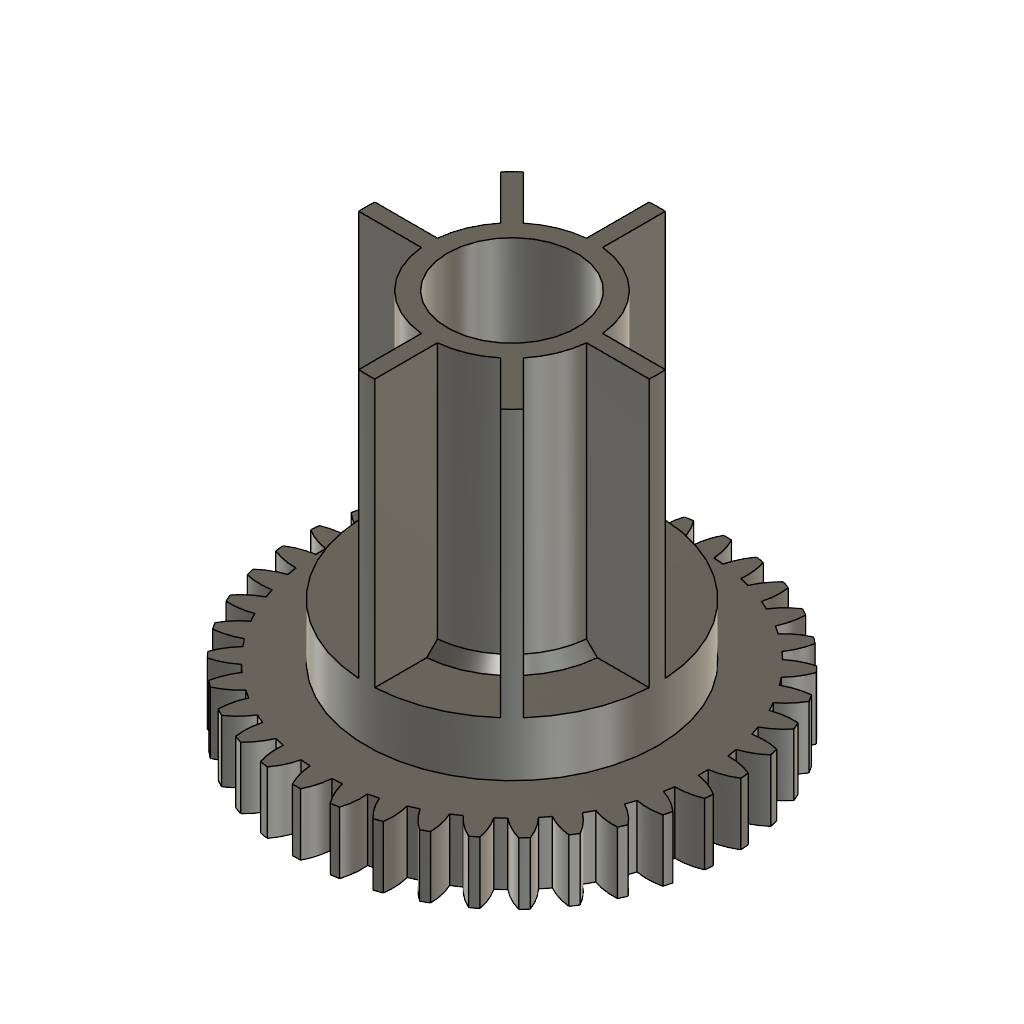
Roue_Store_D27 (Autodesk Fusion 360 design; units mm, degrees)
Autodesk Fusion 360 part; units mm, degrees
sketch "Esquisse1" plane through (0, 0, 0) normal (0, 0, 1) x (1, 0, 0)
  circle A0 centre (0, 0) radius 17.75
  dimension "d1" = 35.5
  measures "d1" diameter of A0
extrude "Extrusion1" add sketch "Esquisse1" along normal blind 5.75
sketch "Esquisse2" plane through (0, 0, 0) normal (0, 0, 1) x (1, 0, 0)
  circle A0 centre (0, 0) radius 13.5
  dimension "d4" = 27
  measures "d4" diameter of A0
extrude "Extrusion2" add sketch "Esquisse2" along normal blind 5.05 from surface at 5.75
sketch "Esquisse3" plane through (0, 0, 0) normal (0, 0, 1) x (1, 0, 0)
  circle A0 centre (0, 0) radius 7.7
  dimension "d8" = 15.4
  measures "d8" diameter of A0
extrude "Extrusion3" add sketch "Esquisse3" along normal blind 24.8 from surface at 10.8
sketch "Esquisse4" plane through (0, 0, 0) normal (0, 0, 1) x (1, 0, 0)
  circle A0 centre (0, 0) radius 11
  dimension "d12" = 22
  measures "d12" diameter of A0
extrude "Extrusion4" cut sketch "Esquisse4" along normal blind 5.5
sketch "Esquisse5" plane through (0, 0, 0) normal (0, 0, 1) x (1, 0, 0)
  circle A0 centre (0, 0) radius 3
  dimension "d15" = 6
  measures "d15" diameter of A0
extrude "Extrusion5" cut sketch "Esquisse5" along normal through all
sketch "Esquisse6" plane through (0, 0, 0) normal (0, 0, 1) x (1, 0, 0)
  circle A0 centre (0, 0) radius 6
  dimension "d17" = 12
  measures "d17" diameter of A0
extrude "Extrusion6" cut sketch "Esquisse6" against normal blind 20 from surface at 35.6
chamfer "Chanfrein1" distance 1 angle 45 1 edges at (-7.1789, 2.7844, 10.8) tangent chain off
chamfer "Chanfrein2" distance 1.4 angle 45 1 edges at (-5.594, 2.1697, 15.6) tangent chain off
sketch "Esquisse7" plane through (0, 0, 0) normal (0, 0, 1) x (1, 0, 0)
  arc A0 (0.3802, 19.9957) -> (-0.3768, 19.9957) centre (0.0017, -0.0007) ccw
  arc A1 (1.0258, 17.4199) -> (-1.0222, 17.4199) centre (0.0018, 0) ccw
  arc A2 (1.0258, 17.4199) -> (0.3802, 19.9957) centre (-4.7875, 17.3315) ccw
  arc A3 (-0.3768, 19.9957) -> (-1.0222, 17.4199) centre (4.7912, 17.3321) ccw
  dimension "d23" = 40
  dimension "d24" = 34.9
  dimension "d25" = 5.814
  dimension "d26" = 0.757
  dimension "d27" = 2.048
  constraint coincident A0.start A2.end
  constraint coincident A1.start A2.start
  constraint coincident A0.end A3.start
  constraint coincident A1.end A3.end
  constraint horizontal A0.start A0.end
  constraint horizontal A1.start A1.end
  constraint equal A2 A3
  measures "d23" diameter of A0
  measures "d24" diameter of A1
  measures "d25" radius of A2
  measures "d26" horizontal distance of A0.start A0.end
  measures "d27" horizontal distance of A1.start A1.end
extrude "Extrusion7" add sketch "Esquisse7" along normal blind 5.75
pattern_circular "Réseau C1" count 38 over 360 about axis through (0, 0, 1.75) along (0, 0, 1) of "Extrusion7"
sketch "Esquisse8" plane through (0, 0, 0) normal (0, 0, 1) x (1, 0, 0)
  arc A0 (13.4792, -0.75) -> (13.4792, 0.75) centre (0, 0) ccw
  arc A1 (6.9597, -0.75) -> (6.9597, 0.75) centre (0, 0) ccw
  line L0 (13.4792, 0.75) -> (6.9597, 0.75)
  line L1 (13.4792, -0.75) -> (6.9597, -0.75)
  dimension "d32" = 27
  dimension "d33" = 14
  dimension "d34" = 1.5
  dimension "d35" = 0.75
  constraint horizontal L0
  constraint horizontal L1
  measures "d32" diameter of A0
  measures "d33" diameter of A1
  measures "d34" vertical distance of A0.start A0.end
  measures "d35" vertical distance of A0.centre A0.end
extrude "Extrusion8" add sketch "Esquisse8" along normal blind 24.8 from surface at 10.8
pattern_circular "Réseau C2" count 4 over 360 about axis through (0, 0, 1.75) along (0, 0, 1) of "Extrusion8"
pattern_circular "Réseau C3" count 2 over 135 about axis through (0, 0, 1.75) along (0, 0, 1) of "Extrusion8"
pattern_circular "Réseau C4" count 2 over 315 about axis through (0, 0, 1.75) along (0, 0, 1) of "Extrusion8"
equation "d19 = -( 20 mm )"
